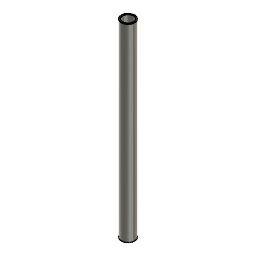
Metal Tube (Autodesk Fusion 360 design; units mm, degrees)
part number: 2025-11-17-16-45-37-665
Autodesk Fusion 360 part; units mm, degrees
sketch "Sketch1" plane through (0, 0, 339.1805) normal (0, 0, 1) x (-1, 0, 0)
  circle A0 centre (35.4997, -19.942) radius 2.5
  circle A1 centre (35.4997, -19.942) radius 2.5
  circle A2 centre (35.4997, -19.942) radius 2
  dimension "d167" = 5
  dimension "d168" = 4
  constraint concentric A0 A1
  constraint concentric A0 A2
  measures "d167" diameter of A0
  measures "d168" diameter of A2
extrude "Extrude1" add sketch "Sketch1" along normal blind 20 and the other way blind 50
